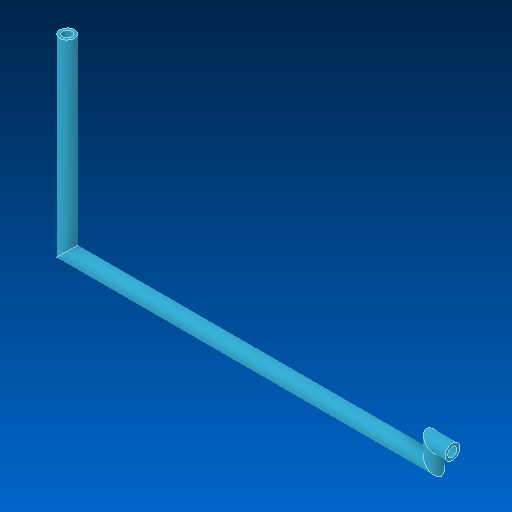
# Autodesk Inventor part: air pump tube
Saved by Autodesk Inventor 2019 (Build 230136000, 136)
## iProperties
Created: 2019-03-21
Part Number: air pump tube
Material: Generic
Document SubType Name: Modeling
Designer: Dell
Density: 1 g/cm^3
Appearance: Turquoise
Mass: 9.64174 g
Surface Area: 129.169 cm^2
Volume: 9.64174 cm^3
Author: Dell
Autodesk Inventor part; units mm, degrees
ref_plane "YZ Plane" through (0, 0, 0) normal (1, 0, 0) x (0, 1, 0)
ref_plane "XZ Plane" through (0, 0, 0) normal (0, 1, 0) x (-1, 0, 0)
ref_plane "XY Plane" through (0, 0, 0) normal (0, 0, 1) x (1, 0, 0)
sketch "Sketch1" plane through (0, 0, 0) normal (1, 0, 0) x (0, 1, 0)
  circle A0 centre (0, 0) radius 4
  circle A1 centre (0, 0) radius 2.5
  dimension "d0" = 8
  dimension "d1" = 5
  constraints: 2 centre point, 2 coincident
  measures "d0" diameter of A0
  measures "d1" diameter of A1
sketch "Sketch2" plane through (0, 0, 0) normal (0, 0, 1) x (1, 0, 0)
  line L0 (0, 0) -> (-9.7756, 0)
  line L1 (-9.7756, 0) -> (-9.7756, -10)
  line L2 (-9.7756, -10) -> (-204.7756, -10)
  line L3 (-204.7756, -10) -> (-204.7756, 90)
  dimension "d4" = 10
  dimension "d5" = 195
  dimension "d6" = 100
  constraints: 8 end point, 2 vertical, 1 horizontal, 1 perpendicular
  measures "d4" distance of L0.end L1.end
  measures "d5" distance of L1.end L2.end
  measures "d6" distance of L2.end L3.end
sweep "Sweep1" add profiles "Sketch1" path "Sketch2"
body "Solid1"
